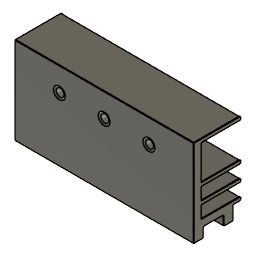
R-2312-45 (Autodesk Fusion 360 design; units mm, degrees)
part number: 2026-02-22-20-59-24-611
Autodesk Fusion 360 part; units mm, degrees
sketch "Sketch1" plane through (0, 0, 0) normal (0, 0, 1) x (1, 0, 0)
  line L0 (22.5, 6) -> (-22.5, 6)
  line L1 (-22.5, 6) -> (-22.5, -6)
  line L2 (-22.5, -6) -> (22.5, -6)
  line L3 (22.5, -6) -> (22.5, 6)
  line L4 (22.5, 6) -> (-22.5, -6) construction
  line L5 (-22.5, 6) -> (22.5, -6) construction
  dimension "d1" = 45
  dimension "d2" = 12
  constraint horizontal L0
  constraint perpendicular L0 L1
  constraint parallel L0 L2
  constraint parallel L1 L3
  constraint coincident L4 origin
  constraint coincident L5 origin
  measures "d1" distance of L1.end L2.end
  measures "d2" distance of L0.end L1.end
extrude "Extrude1" add sketch "Sketch1" along normal blind 22
sketch "Sketch2" plane through (22.5, 0, 0) normal (1, 0, 0) x (0, 1, 0)
  line L0 (-6, 0) -> (6, 0)
  line L1 (6, 0) -> (6, 22)
  line L2 (6, 22) -> (-6, 22)
  line L3 (-6, 22) -> (-6, 0)
  line L4 (-4, 0) -> (-4, 22) construction
  line L5 (-3.5, 0) -> (-3.5, 22) construction
  line L6 (-6, 2.5) -> (6, 2.5) construction
  line L7 (1.5, 0) -> (1.5, 22) construction
  line L8 (4, 0) -> (4, 22) construction
  line L9 (-6, 4.5) -> (6, 4.5) construction
  line L10 (-6, 3.5) -> (6, 3.5) construction
  line L11 (-6, 7.5) -> (6, 7.5) construction
  line L12 (-6, 8.5) -> (6, 8.5) construction
  line L13 (-6, 11.5) -> (6, 11.5) construction
  line L14 (-6, 12.5) -> (6, 12.5) construction
  line L15 (-6, 21) -> (6, 21) construction
  arc A0 (5.4991, 21) -> (5.5, 22) centre (5.5, 21.5) ccw
  arc A1 (5.4989, 11.5) -> (5.4991, 12.5) centre (5.5, 12) ccw
  arc A2 (5.4996, 7.5) -> (5.5, 8.5) centre (5.5, 8) ccw
  arc A3 (5.4994, 3.5) -> (5.4996, 4.5) centre (5.5, 4) ccw
  arc A4 (3.8, 0) -> (4, 0.2) centre (3.8, 0.2) ccw
  arc A5 (1.5, 0.2001) -> (1.7, 0) centre (1.7, 0.2) ccw
  arc A6 (1.5, 2.3) -> (1.3, 2.5) centre (1.3, 2.3) ccw
  arc A7 (-3.3, 2.5) -> (-3.5, 2.3) centre (-3.3, 2.3) ccw
  arc A8 (-3.7, 0) -> (-3.5, 0.2) centre (-3.7, 0.2) ccw
  line L16 (4, 0.2) -> (4, 3.5)
  line L17 (4, 3.5) -> (5.4994, 3.5)
  line L18 (5.4996, 4.5) -> (-4, 4.5)
  line L19 (1.7, 0) -> (3.8, 0)
  line L20 (1.5, 0.2001) -> (1.5, 2.3)
  line L21 (1.3, 2.5) -> (-3.3, 2.5)
  line L22 (-3.5, 0.2) -> (-3.5, 2.3)
  line L23 (-3.7, 0) -> (-6, 0)
  line L24 (-6, 0) -> (-6, 22)
  line L25 (-6, 22) -> (5.5, 22)
  line L26 (5.4991, 21) -> (-4, 21)
  line L27 (-4, 21) -> (-4, 12.5)
  line L28 (-4, 12.5) -> (5.4991, 12.5)
  line L29 (5.4989, 11.5) -> (-4, 11.5)
  line L30 (-4, 11.5) -> (-4, 8.5)
  line L31 (-4, 8.5) -> (5.5, 8.5)
  line L32 (5.4996, 7.5) -> (-4, 7.5)
  line L33 (-4, 4.5) -> (-4, 7.5)
  dimension "d5" = 22
  dimension "d6" = 2
  dimension "d7" = 22
  dimension "d8" = 2.5
  dimension "d9" = 12
  dimension "d10" = 2.5
  dimension "d11" = 22
  dimension "d12" = 5
  dimension "d13" = 22
  dimension "d14" = 2.5
  dimension "d15" = 12
  dimension "d16" = 2
  dimension "d17" = 1
  dimension "d18" = 3
  dimension "d19" = 1
  dimension "d20" = 3
  dimension "d21" = 1
  dimension "d22" = 1
  constraint vertical L4
  constraint coincident L0 L4.start
  constraint vertical L5
  constraint coincident L0 L5.start
  constraint horizontal L6
  constraint coincident L3 L6.start
  constraint vertical L7
  constraint coincident L0 L7.start
  constraint vertical L8
  constraint coincident L0 L8.start
  constraint horizontal L9
  constraint coincident L3 L9.start
  constraint coincident L3 L10.start
  constraint coincident L1 L10.end
  constraint perpendicular L1 L10
  constraint coincident L3 L11.start
  constraint coincident L1 L11.end
  constraint perpendicular L1 L11
  constraint coincident L3 L12.start
  constraint coincident L1 L12.end
  constraint perpendicular L1 L12
  constraint coincident L3 L13.start
  constraint coincident L1 L13.end
  constraint perpendicular L1 L13
  constraint coincident L3 L14.start
  constraint coincident L1 L14.end
  constraint perpendicular L1 L14
  constraint coincident L3 L15.start
  constraint coincident L1 L15.end
  constraint perpendicular L1 L15
  constraint coincident L15 A0.start
  constraint coincident L2 A0.end
  constraint coincident L13 A1.start
  constraint coincident L14 A1.end
  constraint coincident L11 A2.start
  constraint coincident L12 A2.end
  constraint coincident L10 A3.start
  constraint coincident L9 A3.end
  constraint coincident L0 A4.start
  constraint coincident L8 A4.end
  constraint coincident L7 A5.start
  constraint coincident L0 A5.end
  constraint coincident L6 A6.end
  constraint coincident L7 A6.start
  constraint coincident L5 A7.end
  constraint coincident L6 A7.start
  constraint coincident L0 A8.start
  constraint coincident L5 A8.end
  constraint coincident L10 L16.end
  constraint coincident L8 L16.end
  constraint coincident L4 L18.end
  constraint coincident L9 L18.end
  constraint tangent A4 L19
  constraint tangent A6 L20
  constraint tangent A6 L21
  constraint tangent A7 L22
  constraint coincident L0.start L3.end
  constraint tangent A8 L23
  constraint coincident L2.end L3.start
  constraint tangent A0 L25
  constraint coincident L4 L26.end
  constraint coincident L15 L26.end
  constraint coincident L4 L27.end
  constraint coincident L14 L27.end
  constraint coincident L13 L29.end
  constraint coincident L4 L29.end
  constraint coincident L12 L30.end
  constraint coincident L4 L30.end
  constraint tangent A2 L31
  constraint coincident L4 L32.end
  constraint coincident L11 L32.end
  measures "d5" distance of L4.start L4.end
  measures "d6" distance of L3 L4
  measures "d7" distance of L5.start L5.end
  measures "d8" distance of L3 L5
  measures "d9" distance of L6.start L6.end
  measures "d10" distance of L0 L6
  measures "d11" distance of L7.start L7.end
  measures "d12" distance of L5 L7
  measures "d13" distance of L8.start L8.end
  measures "d14" distance of L7 L8
  measures "d15" distance of L9.start L9.end
  measures "d16" distance of L6 L9
  measures "d17" distance of L6 L10
  measures "d18" distance of L9 L11
  measures "d19" distance of L11 L12
  measures "d20" distance of L12 L13
  measures "d21" distance of L13 L14
  measures "d22" distance of L2 L15
extrude "Extrude2" cut sketch "Sketch2" against normal blind 45 contours L0 A5 A6 A7 A8 L20 L21 L22 | L1 L2 A0 | L0 L1 A3 A4 L16 L17 | L1 A0 A1 L26 L27 L28 | L1 A1 A2 L29 L30 L31 | L1 A2 A3 L18 L32 L33
sketch "Sketch3" plane through (0, -6, 0) normal (0, -1, 0) x (1, 0, 0)
  line L0 (-22.5, 0) -> (22.5, 0)
  line L1 (22.5, 0) -> (22.5, 22)
  line L2 (22.5, 22) -> (-22.5, 22)
  line L3 (-22.5, 22) -> (-22.5, 0)
  line L4 (0, 0) -> (0, 22) construction
  line L5 (11.25, 0) -> (11.25, 22) construction
  line L6 (-11.25, 0) -> (-11.25, 22) construction
  line L7 (-22.5, 16) -> (22.5, 16) construction
  circle A0 centre (-11.25, 16) radius 1
  circle A1 centre (0, 16) radius 1
  circle A2 centre (11.25, 16) radius 1
  point P0 (-11.25, 16)
  point P1 (0, 16)
  point P2 (11.25, 16)
  dimension "d25" = 22
  dimension "d26" = 22
  dimension "d27" = 22
  dimension "d28" = 11.25
  dimension "d29" = 11.25
  dimension "d30" = 45
  dimension "d31" = 6
  dimension "d32" = 2
  dimension "d33" = 2
  dimension "d34" = 2
  constraint vertical L4
  constraint coincident L4.start origin
  constraint vertical L5
  constraint coincident L0 L5.start
  constraint vertical L6
  constraint coincident L0 L6.start
  constraint horizontal L7
  constraint coincident L3 L7.start
  constraint coincident L7 P0
  constraint coincident L6 P0
  constraint midpoint L7 P1
  constraint coincident L7 P2
  constraint coincident L5 P2
  constraint coincident P0 A0.centre
  constraint coincident P1 A1.centre
  constraint coincident P2 A2.centre
  measures "d25" distance of L4.start L4.end
  measures "d26" distance of L5.start L5.end
  measures "d27" distance of L6.start L6.end
  measures "d28" distance of L4 L6
  measures "d29" distance of L4 L5
  measures "d30" distance of L7.start L7.end
  measures "d31" distance of L2 L7
  measures "d32" diameter of A0
  measures "d33" diameter of A1
  measures "d34" diameter of A2
extrude "Extrude3" cut sketch "Sketch3" against normal blind 2 contours A0 | A1 | A2
chamfer "Chamfer1" distance 0.5 distance2 0.2 3 edges at (-12.1823, -6, 16.3616) (-0.9323, -6, 16.3616) (10.3177, -6, 16.3616) measured on face at (-0.0249, -6, 5.0009) measured on face at (-0.0249, -6, 5.0009) measured on face at (-0.0249, -6, 5.0009)
fillet "Fillet1" radius 0.1 56 edges at (-22.5, -6, 11) (-22.5, 0.7496, 21) (-22.5, 6, 21.4996) (-22.5, -0.25, 22) (-22.5, -4, 16.75) (-22.5, 0.7496, 12.5) (-22.5, 6, 11.9999) (-22.5, 0.7494, 11.5) (-22.5, -4, 10) (-22.5, 0.75, 8.5) (-22.5, 6, 7.9998) (-22.5, 0.7498, 7.5) (-22.5, -4, 6) (0, -6, 0) (0, -6, 22) (22.5, -6, 11) (22.5, -0.25, 22) (22.5, 6, 21.4996) (22.5, 0.7496, 21) (22.5, -4, 16.75) (22.5, 0.7494, 11.5) (22.5, 6, 11.9999) (22.5, 0.7496, 12.5) (22.5, -4, 10) (22.5, 0.7498, 7.5) (22.5, 6, 7.9998) (22.5, 0.75, 8.5) (22.5, -4, 6) (22.5, 4.7497, 3.5) (22.5, 6, 3.9999) (22.5, 0.7498, 4.5) (22.5, -4.85, 0) (22.5, -3.5586, 0.0586) (22.5, -3.5, 1.25) (22.5, -3.4414, 2.4414) (22.5, -1, 2.5) (22.5, 1.4414, 2.4414) (22.5, 1.5, 1.2501) (22.5, 1.5585, 0.0586) (22.5, 2.75, 0) (22.5, 3.9414, 0.0586) (22.5, 4, 1.85) (-22.5, 0.7498, 4.5) (-22.5, 6, 3.9999) (-22.5, 4.7497, 3.5) (-22.5, 4, 1.85) (-22.5, 3.9414, 0.0586) (-22.5, 2.75, 0) (-22.5, 1.5585, 0.0586) (-22.5, 1.5, 1.2501) (-22.5, 1.4414, 2.4414) (-22.5, -1, 2.5) (-22.5, -3.4414, 2.4414) (-22.5, -3.5, 1.25) (-22.5, -3.5586, 0.0586) (-22.5, -4.85, 0)
